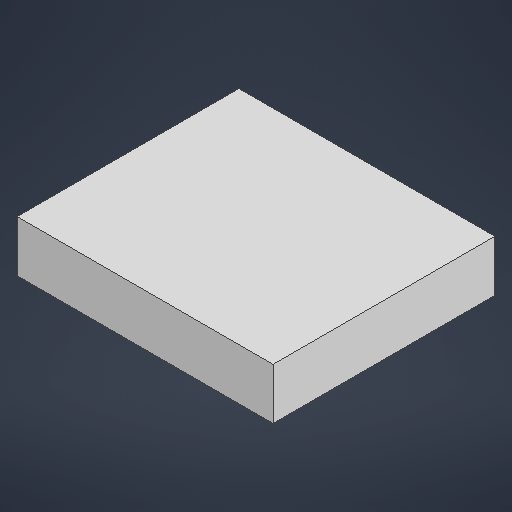
# Autodesk Inventor part: dummy_i2s_mic
Saved by Autodesk Inventor 2027.1 (Build 311270010, 270A)
## iProperties
Created: 2026-10-29
Part Number: dummy_i2s_mic
Material: Generic
Document SubType Name: Modeling
Designer: shyan
Density: 1 g/cm^3
Appearance: Default
Author: shyan
Autodesk Inventor part; units mm, degrees
ref_plane "YZ Plane" through (0, 0, 0) normal (1, 0, 0) x (0, 1, 0)
ref_plane "XZ Plane" through (0, 0, 0) normal (0, 1, 0) x (-1, 0, 0)
ref_plane "XY Plane" through (0, 0, 0) normal (0, 0, 1) x (1, 0, 0)
sketch "Sketch1" plane through (0, 0, 0) normal (0, 0, 1) x (1, 0, 0)
  line L0 (-7.5, -1.5) -> (7.5, -1.5)
  line L1 (7.5, -1.5) -> (7.5, 1.5)
  line L2 (7.5, 1.5) -> (-7.5, 1.5)
  line L3 (-7.5, 1.5) -> (-7.5, -1.5)
  constraints: 8 end point, 2 parallel, 1 horizontal, 1 perpendicular
extrude "Block" add sketch "Sketch1" along normal blind 13
body "Solid1"
